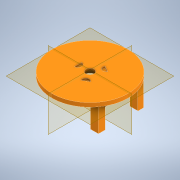
# Autodesk Inventor part: Closure
Saved by Autodesk Inventor 2021 (Build 250183000, 183)
## iProperties
Created: 2026-04-22
Part Number: Closure
Material: Generic
Document SubType Name: Modeling
Designer: Admin
Density: 1 g/cm^3
Appearance: Orange
Author: Admin
Autodesk Inventor part; units mm, degrees
sketch "Sketch1" plane through (0, 0, 0) normal (0, 1, 0) x (-1, 0, 0)
  circle A0 centre (0, 0) radius 47.5
  dimension "d0" = 95
  constraints: 1 centre point, 1 coincident
  measures "d0" diameter of A0
extrude "Extrusion1" add sketch "Sketch1" along normal blind 5
sketch "Sketch2" plane through (0, 5, 0) normal (0, 1, 0) x (1, 0, 0)
  circle A0 centre (0, 0) radius 10.5 construction
  line L0 (0, 66.5) -> (0, -66.5) projected
  circle A1 centre (7.5, 12.9904) radius 4.5
  line L1 (0, 0) -> (7.5, 12.9904)
  line L2 (66.5, 0) -> (-66.5, 0) projected
  line L3 (11.3971, 10.7404) -> (3.6029, 15.2404)
  dimension "d3" = 21
  dimension "d9" = 9
  dimension "d10" = 30
  constraints: 4 end point, 3 midpoint, 2 centre point, 2 point on circle, 1 perpendicular, 1 tangent
  measures "d3" diameter of A0
  measures "d9" diameter of A1
  measures "d10" angle of L0 L1
extrude "Extrusion2" cut sketch "Sketch2" against normal blind 2 contours L3 L1 A1 | A1 L1 L3
pattern_circular "Circular Pattern1" count 3 over 360 about axis through (0, -10, 0) along (0, 1, 0) of "Extrusion2"
sketch "Sketch3" plane through (0, 0, 0) normal (0, -1, 0) x (1, 0, 0)
  line L0 (22.5, -34) -> (32.5, -34)
  line L1 (32.5, -34) -> (32.5, 22)
  line L2 (32.5, 22) -> (22.5, 22)
  line L3 (22.5, 22) -> (22.5, -34)
  line L4 (22.5, -34) -> (32.5, 22) construction
  line L5 (32.5, -34) -> (22.5, 22) construction
  line L6 (0, 66.5) -> (0, -66.5) projected
  line L7 (-66.5, 0) -> (66.5, 0) projected
  circle A0 centre (0, 0) radius 47.5 projected
  point P0 (27.5, -6)
  dimension "d14" = 10
  dimension "d16" = 22.5
  dimension "d17" = 22
  dimension "d23" = 34
  constraints: 12 end point, 2 midpoint, 2 parallel, 1 horizontal, 1 perpendicular
  measures "d14" distance of L1.end L2.end
  measures "d16" distance between parallel lines of L3 L6
  measures "d17" distance between parallel lines of L7 L2
  measures "d23" distance between parallel lines of L7 L0
extrude "Extrusion3" add sketch "Sketch3" along normal blind 35 contours L3 L7 L1 L0 | L3 L2 L1 L7
sketch "Sketch4" plane through (0, 0, 0) normal (0, -1, 0) x (1, 0, 0)
  circle A0 centre (0, 0) radius 5
  dimension "d20" = 10
  constraints: 1 centre point, 1 coincident
  measures "d20" diameter of A0
extrude "Extrusion4" cut sketch "Sketch4" against normal blind 30
sketch "Sketch5" plane through (32.5, 0, 22) normal (1, 0, 0) x (0, 0, -1)
  line L0 (56, -35) -> (0, -35) projected
  line L1 (49.3, -35) -> (8.3, -35)
  line L2 (8.3, -35) -> (8.3, -10)
  line L3 (8.3, -10) -> (49.3, -10)
  line L4 (49.3, -10) -> (49.3, -35)
  line L5 (56, 0) -> (56, -35) projected
  line L6 (0, 0) -> (0, -35) projected
  point P0 (22, 0)
  point P1 (8.3, -35)
  dimension "d24" = 6.7
  dimension "d25" = 8.3
  dimension "d26" = 25
  constraints: 8 end point, 2 parallel, 1 horizontal, 1 perpendicular, 1 point on line
  measures "d24" distance between parallel lines of L5 L4
  measures "d25" distance between parallel lines of L6 L2
  measures "d26" distance between parallel lines of L0 L3
extrude "Extrusion5" cut sketch "Sketch5" against normal blind 30
body "Solid1"
